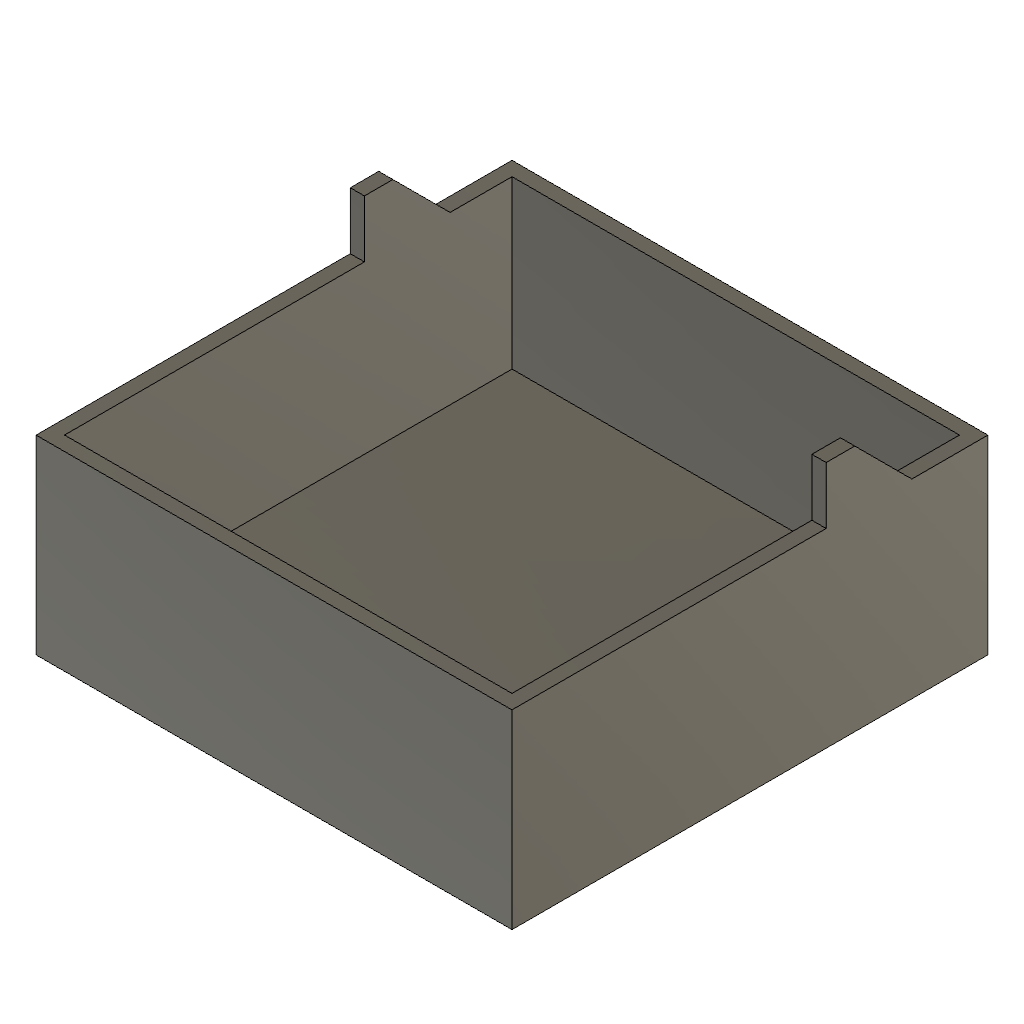
Drawers (Autodesk Fusion 360 design; units mm, degrees)
Autodesk Fusion 360 part; units mm, degrees
sketch "Sketch1" plane through (0, 0, 0) normal (0, 0, 1) x (1, 0, 0)
  line L0 (50, 50) -> (-50, 50)
  line L1 (-50, 50) -> (-50, -50)
  line L2 (-50, -50) -> (50, -50)
  line L3 (50, -50) -> (50, 50)
  line L4 (50, 50) -> (-50, -50) construction
  line L5 (-50, 50) -> (50, -50) construction
  line L6 (-47, -47) -> (47, -47)
  line L7 (47, -47) -> (47, 47)
  line L8 (47, 47) -> (-47, 47)
  line L9 (-47, 47) -> (-47, -47)
  dimension "d1" = 100
  dimension "d2" = 100
  dimension "d3" = -3
  constraint horizontal L0
  constraint perpendicular L0 L1
  constraint parallel L0 L2
  constraint parallel L1 L3
  constraint coincident L4 origin
  constraint coincident L5 origin
  measures "d1" distance of L1.end L2.end
  measures "d2" distance of L0.end L1.end
extrude "Extrude1" add sketch "Sketch1" along normal blind 40
extrude "Extrude2" add sketch "Sketch1" along normal blind 5 contours L6 L7 L8 L9
sketch "Sketch5" plane through (0, 0, 40) normal (0, 0, 1) x (-1, 0, 0)
  line L0 (50, -50) -> (50, 50)
  line L1 (-47, -47) -> (-47, 47)
  line L2 (47, -22) -> (50, -22)
  line L3 (50, -22) -> (50, -16)
  line L4 (50, -16) -> (47, -16)
  line L5 (47, -16) -> (47, -22)
  line L6 (47, 47) -> (47, -47)
  line L7 (47, -47) -> (-47, -47)
  line L8 (-47, -22) -> (-50, -22)
  line L9 (-50, -22) -> (-50, -16)
  line L10 (-50, -16) -> (-47, -16)
  line L11 (-47, -16) -> (-47, -22)
  dimension "d44" = 6
  dimension "d45" = 25
  dimension "d46" = 6
  dimension "d47" = 25
  constraint horizontal L2
  constraint vertical L3
  constraint horizontal L4
  constraint vertical L5
  constraint coincident L2.start L6
  constraint horizontal L8
  constraint vertical L9
  constraint horizontal L10
  constraint vertical L11
  constraint coincident L1 L8.start
  measures "d44" distance of L2.start L4.end
  measures "d45" distance of L2 L7
  measures "d46" distance of L8.start L10.end
  measures "d47" distance of L7 L8
extrude "Extrude7" add sketch "Sketch5" along normal blind 12
sketch "Sketch8" plane through (50, 0, 0) normal (1, 0, 0) x (0, 1, 0)
  line L0 (-50, 0) -> (50, 0)
  line L1 (50, 0) -> (50, 40)
  line L2 (50, 40) -> (22, 40)
  line L3 (22, 40) -> (22, 52)
  line L4 (22, 52) -> (16, 52)
  line L5 (16, 52) -> (16, 40)
  line L6 (16, 40) -> (-50, 40)
  line L7 (-50, 40) -> (-50, 0)
  line L8 (22, 52) -> (41.5376, 32.4624)
  line L9 (22, 52) -> (41.1303, 52) construction
  dimension "d48" = 45
  constraint horizontal L9
  constraint coincident L3.end L4.start
  measures "d48" angle of L8 L9
sketch "Sketch10" plane through (-50, 0, 0) normal (-1, 0, 0) x (0, -1, 0)
  line L0 (-50, 0) -> (50, 0)
  line L1 (50, 0) -> (50, 40)
  line L2 (50, 40) -> (-16, 40)
  line L3 (-16, 40) -> (-16, 52)
  line L4 (-16, 52) -> (-22, 52)
  line L5 (-22, 52) -> (-22, 40)
  line L6 (-22, 40) -> (-50, 40)
  line L7 (-50, 40) -> (-50, 0)
  line L8 (-22, 52) -> (-41.5376, 32.4624)
  line L9 (-22, 52) -> (-41.5376, 32.4624)
  point P0 (-41.5376, 32.4624)
  constraint coincident L4.end L5.start
  constraint coincident P0 L8.end
extrude "Extrude10" add sketch "Sketch10" against normal up to surface (3 mm away) contours L5 L6 L8 L9
extrude "Extrude11" add sketch "Sketch8" against normal blind 3 contours L2 L3 L8
